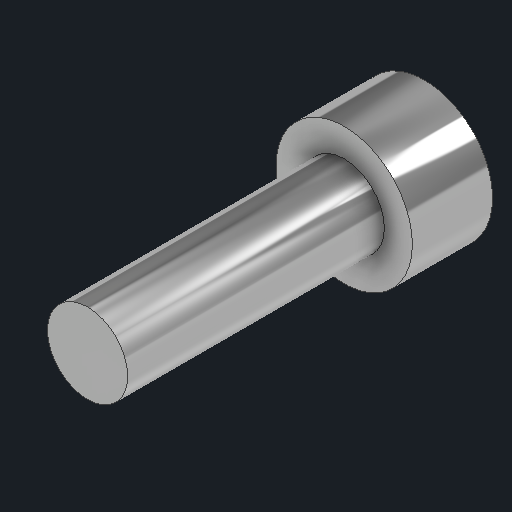
# Autodesk Inventor part: m5_shcs_16
Saved by Autodesk Inventor 2027.1 (Build 311270010, 270A)
## iProperties
Created: 2026-11-03
Part Number: m5_shcs_16
Material: Generic
Description: M5x16 socket head cap screw (head 8.5, 4 mm hex)
Document SubType Name: Modeling
Designer: Claude (from photos)
Density: 1 g/cm^3
Appearance: Stainless Steel - Bright
Author: alexg
Autodesk Inventor part; units mm, degrees
ref_plane "YZ Plane" through (0, 0, 0) normal (1, 0, 0) x (0, 1, 0)
ref_plane "Work Plane1" through (0, 0, -5) normal (0, 0, 1) x (1, 0, 0)
sketch "Head 8.5 sketch" plane through (0, 0, -5) normal (0, 0, 1) x (1, 0, 0)
  circle A0 centre (0, 0) radius 4.25
  constraints: 1 centre point
extrude "Head 8.5" add sketch "Head 8.5 sketch" along normal blind 5
ref_plane "Work Plane2" through (0, 0, -5) normal (0, 0, 1) x (1, 0, 0)
sketch "Hex socket 4 sketch" plane through (0, 0, -5) normal (0, 0, 1) x (1, 0, 0)
  line L0 (2.3094, 0) -> (1.1547, 2)
  line L1 (1.1547, 2) -> (-1.1547, 2)
  line L2 (-1.1547, 2) -> (-2.3094, 0)
  line L3 (-2.3094, 0) -> (-1.1547, -2)
  line L4 (-1.1547, -2) -> (1.1547, -2)
  line L5 (1.1547, -2) -> (2.3094, 0)
  constraints: 12 end point
extrude "Hex socket 4" cut sketch "Hex socket 4 sketch" along normal blind 2.5
sketch "Shank M5x16 sketch" plane through (0, 0, 0) normal (0, 0, 1) x (1, 0, 0)
  circle A0 centre (0, 0) radius 2.5
  constraints: 1 centre point
extrude "Shank M5x16" add sketch "Shank M5x16 sketch" along normal blind 16
body "Solid1"
